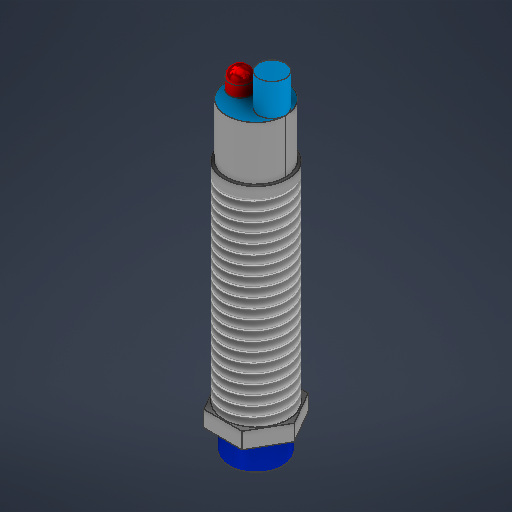
# Autodesk Inventor part: lj12
Saved by Autodesk Inventor 2026.2 (Build 302298010, 298A)
## iProperties
Created: 2026-04-03
Part Number: lj12
Material: 일반
Document SubType Name: Modeling
Designer: work
Density: 1 g/cm^3
Appearance: 크롬 - 연마 검은색
Author: work
Autodesk Inventor part; units mm, degrees
ref_plane "YZ Plane" through (0, 0, 0) normal (1, 0, 0) x (0, 1, 0)
ref_plane "XZ Plane" through (0, 0, 0) normal (0, 1, 0) x (-1, 0, 0)
ref_plane "XY Plane" through (0, 0, 0) normal (0, 0, 1) x (1, 0, 0)
sketch "스케치1" plane through (0, 0, 0) normal (0, 1, 0) x (-1, 0, 0)
  circle A0 centre (0, 0) radius 6
  dimension "d0" = 12
  constraints: 1 centre point, 1 coincident
  measures "d0" diameter of A0
extrude "돌출1" add sketch "스케치1" along normal blind 52
thread "스레드1" size "M12x1.75" class "6g" standard "ANSI Metric M Profile" length 40
sketch "스케치2" plane through (0, 0, 0) normal (0, -1, 0) x (1, 0, 0)
  line L0 (3.5796, 6.2) -> (7.1591, 0)
  line L1 (7.1591, 0) -> (3.5796, -6.2)
  line L2 (3.5796, -6.2) -> (-3.5796, -6.2)
  line L3 (-3.5796, -6.2) -> (-7.1591, 0)
  line L4 (-7.1591, 0) -> (-3.5796, 6.2)
  line L5 (-3.5796, 6.2) -> (3.5796, 6.2)
  line L6 (0, 0) -> (0, 6.2) construction
  dimension "d6" = 6.2
  constraints: 14 end point, 1 coincident, 1 midpoint, 1 vertical, 13 other
  measures "d6" distance of L6.start L6.end
extrude "돌출2" add sketch "스케치2" against normal blind 3
sketch "스케치3" plane through (0, 0, 0) normal (0, -1, 0) x (1, 0, 0)
  circle A0 centre (0, 0) radius 6 projected
  circle A1 centre (0, 0) radius 5
  dimension "d9" = 10
  constraints: 1 centre point, 1 coincident
  measures "d9" diameter of A1
extrude "돌출3" add sketch "스케치3" along normal blind 5 contours A1
sketch "스케치4" plane through (0, 52, 0) normal (0, 1, 0) x (1, 0, 0)
  line L0 (0, 0) -> (3, 0) construction
  circle A0 centre (3, 0) radius 2.5
  dimension "d12" = 3
  dimension "d13" = 5
  constraints: 2 end point, 1 centre point, 1 coincident, 1 horizontal
  measures "d12" distance of L0.start L0.end
  measures "d13" diameter of A0
extrude "돌출4" add sketch "스케치4" along normal blind 6
sketch "스케치5" plane through (0, 52, 0) normal (0, 1, 0) x (1, 0, 0)
  circle A0 centre (-3, 0) radius 2
  circle A1 centre (3, 0) radius 2.5 projected
  point P0 (0, 0)
  dimension "d16" = 4
  dimension "d17" = 6
  constraints: 1 centre point, 1 horizontal alignment
  measures "d16" diameter of A0
  measures "d17" distance of point (3, 0) A0.centre
extrude "돌출5" add sketch "스케치5" along normal blind 4 contours A0
fillet "모깎기1" radius 2 1 edges at (-5, 56, 0)
sketch "스케치6" plane through (0, 52, 0) normal (0, 1, 0) x (1, 0, 0)
  circle A0 centre (0, 0) radius 5.5
  circle A1 centre (-3, 0) radius 2 projected
  circle A2 centre (0, 0) radius 6 projected
  circle A3 centre (3, 0) radius 2.5 projected
  point P0 (5.0417, -2.1981)
  point P1 (5.5, 0)
  dimension "d21" = 11
  constraints: 1 centre point, 1 coincident
  measures "d21" diameter of A0
extrude "돌출6" cut sketch "스케치6" against normal blind 10
